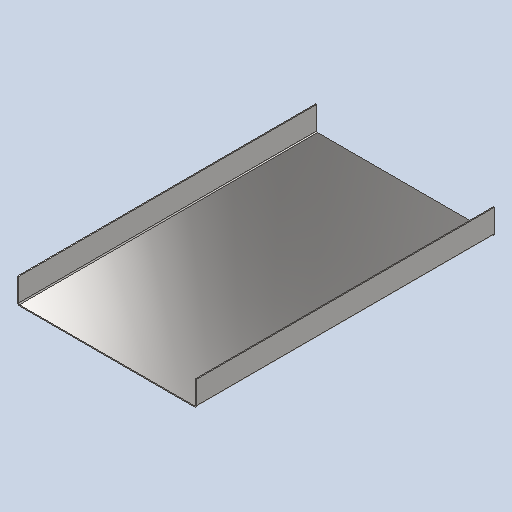
# Autodesk Inventor part: RDS-1204 Bunker Tray
Saved by Autodesk Inventor 2026.2 (Build 302298000, 298)
## iProperties
Created: 2026-10-18
Part Number: RDS-1204 Bunker Tray
Material: Stainless Steel, Austenitic
Description: Bunker bag tray, channel, AISI 304 2 mm; size to 25 kg bag (confirm)
Document SubType Name: Sheet Metal
Designer: admin
Stock Number: Бункер — лоток под мешок (швеллер)
Density: 8 g/cm^3
Flat Pattern Width: 45.3048 cm
Flat Pattern Length: 60 cm
Flat Pattern Area: 2718.29 cm^2
Sheet Metal Rule: Default
Sheet Metal Width: 453,048 mm
Sheet Metal Length: 600,000 mm
Sheet Metal Area: 271828,672 mm^2
Appearance: Semi-Polished
Author: admin
Autodesk Inventor part; units mm, degrees
ref_plane "YZ Plane" through (0, 0, 0) normal (1, 0, 0) x (0, 1, 0)
ref_plane "XZ Plane" through (0, 0, 0) normal (0, 1, 0) x (-1, 0, 0)
ref_plane "XY Plane" through (0, 0, 0) normal (0, 0, 1) x (1, 0, 0)
sketch "Sketch1" plane through (0, 0, 0) normal (0, 1, 0) x (-1, 0, 0)
  line L0 (158, -300) -> (-202, -300)
  line L1 (-202, -300) -> (-202, 300)
  line L2 (-202, 300) -> (158, 300)
  line L3 (158, 300) -> (158, -300)
  dimension "d0" = 360
  dimension "d1" = 600
  measures "d0" distance of L0.start L0.end
  measures "d1" distance of L0.end L1.end
extrude "Plate1" add sketch "Sketch1" along normal blind 2
sketch "Sketch2" plane through (200, 0, -300) normal (1, 0, 0) x (0, 1, 0)
  line L0 (0, 600) -> (0, 0)
  line L1 (0, 0) -> (50, 0)
  line L2 (50, 0) -> (50, 600)
  line L3 (50, 600) -> (0, 600)
  constraints: 6 end point, 1 horizontal, 1 perpendicular, 1 vertical
edge flange "Flange1" height 50 angle 90 thickness 2 bend radius 2 thickness toward (1, 0, 0) relief tear relief width 2 relief depth 1 corner gap 2 corner form 0 edges at (202, 2, 0) (-158, 2, 0) wall of the first edge with corners at (200, 0, 300) (200, 0, -300) (200, 50, -300) (200, 50, 300)
bend "Bend1"
corner "Corner1"
equation "\"d0\" = Tray1204_Width"
equation "\"d1\" = Tray1204_Length"
equation "\"d2\" = Thickness"
equation "\"d3\" = Thickness"
equation "\"d4\" = 0.5 * Thickness"
equation "\"d5\" = 2 * Thickness"
equation "\"d6\" = Thickness"
equation "\"d7\" = Tray1204_Flange_Height"
equation "\"d9\" = Thickness"
equation "\"d10\" = 4 * Thickness"
equation "\"d12\" = JacobiRadiusSize"
equation "\"BendRadius\" = Thickness"
equation "\"BendReliefWidth\" = Thickness"
equation "\"BendReliefDepth\" = 0.5 * Thickness"
equation "\"CornerReliefSize\" = 4 * Thickness"
equation "\"MinimumRemnant\" = 2 * Thickness"
equation "\"TransitionRadius\" = BendRadius"
equation "\"JacobiRadiusSize\" = BendRadius"
equation "\"GapSize\" = Thickness"
equation "\"Tray1204_Width\" = 360"
equation "\"Tray1204_Length\" = 600"
equation "\"Thickness\" = 2"
equation "\"Tray1204_Flange_Height\" = 50"
body "Solid1"
